ControlBox (Autodesk Fusion 360 design; units mm, degrees)
Autodesk Fusion 360 part; units mm, degrees
sketch "Sketch1" plane through (0, 0, 0) normal (0, 0, 1) x (1, 0, 0)
  line L0 (57.5, -137.5) -> (-57.5, -137.5)
  line L1 (-57.5, -137.5) -> (-57.5, 137.5)
  line L2 (-57.5, 137.5) -> (57.5, 137.5)
  line L3 (57.5, 137.5) -> (57.5, -137.5)
  line L4 (57.5, -137.5) -> (-57.5, 137.5) construction
  line L5 (-57.5, -137.5) -> (57.5, 137.5) construction
  line L6 (60, -140) -> (-60, -140)
  line L7 (-60, -140) -> (-60, 140)
  line L8 (-60, 140) -> (60, 140)
  line L9 (60, 140) -> (60, -140)
  line L10 (60, -140) -> (-60, 140) construction
  line L11 (-60, -140) -> (60, 140) construction
  dimension "d1" = 115
  dimension "d2" = 275
  dimension "d3" = 280
  dimension "d4" = 120
  constraint perpendicular L0 L1
  constraint parallel L0 L2
  constraint parallel L1 L3
  constraint horizontal L0
  constraint coincident L4 origin
  constraint coincident L5 origin
  constraint perpendicular L6 L7
  constraint parallel L6 L8
  constraint parallel L7 L9
  constraint horizontal L6
  constraint coincident L10 origin
  constraint coincident L11 origin
  measures "d1" distance of L1.end L2.end
  measures "d2" distance of L0.end L1.end
  measures "d3" distance of L6.end L7.end
  measures "d4" distance of L7.end L8.end
extrude "Extrude1" add sketch "Sketch1" along normal blind 2.5 contours L0 L1 L2 L3 | L6 L7 L8 L9
sketch "Sketch2" plane through (0, 0, 2.5) normal (0, 0, 1) x (1, 0, 0)
  line L0 (60, 140) -> (-60, 140)
  line L1 (-60, 140) -> (-60, -140)
  line L2 (-60, -140) -> (60, -140)
  line L3 (60, -140) -> (60, 140)
  line L4 (57.5, -137.5) -> (-57.5, -137.5)
  line L5 (-57.5, -137.5) -> (-57.5, 137.5)
  line L6 (-57.5, 137.5) -> (57.5, 137.5)
  line L7 (57.5, 137.5) -> (57.5, -137.5)
  line L8 (57.5, -137.5) -> (-57.5, 137.5) construction
  line L9 (-57.5, -137.5) -> (57.5, 137.5) construction
  dimension "d7" = 115
  dimension "d8" = 275
  constraint perpendicular L4 L5
  constraint parallel L4 L6
  constraint parallel L5 L7
  constraint horizontal L4
  constraint coincident L8 origin
  constraint coincident L9 origin
  measures "d7" distance of L5.end L6.end
  measures "d8" distance of L4.end L5.end
extrude "Extrude2" add sketch "Sketch2" along normal blind 50
sketch "Sketch3" plane through (0, -140, 0) normal (0, -1, 0) x (1, 0, 0)
  line L0 (-60, 0) -> (60, 0)
  line L1 (60, 0) -> (60, 52.5)
  line L2 (60, 52.5) -> (-60, 52.5)
  line L3 (-60, 52.5) -> (-60, 0)
extrude "Extrude3" add sketch "Sketch3" along normal blind 4
sketch "Sketch4" plane through (0, -144, 0) normal (0, -1, 0) x (1, 0, 0)
  line L0 (-60, 52.5) -> (-60, 0)
  line L1 (-60, 0) -> (60, 0)
  line L2 (60, 0) -> (60, 52.5)
  line L3 (60, 52.5) -> (-60, 52.5)
  line L4 (40.0928, 9.9) -> (13.3428, 9.9)
  line L5 (13.3428, 9.9) -> (13.3428, 28.5)
  line L6 (13.3428, 28.5) -> (40.0928, 28.5)
  line L7 (40.0928, 28.5) -> (40.0928, 9.9)
  line L8 (51.7178, 8.325) -> (1.7178, 8.325)
  line L9 (1.7178, 30.175) -> (51.7178, 30.175)
  line L10 (51.7178, 30.175) -> (51.7178, 8.325)
  line L11 (40.0928, 30.175) -> (42.8928, 30.175)
  line L12 (40.0928, 19.2) -> (46.5928, 19.2)
  line L13 (13.3428, 19.2) -> (6.8428, 19.2)
  circle A0 centre (6.8428, 19.2) radius 2
  circle A1 centre (46.5928, 19.2) radius 2
  line L14 (46.5928, 19.2) -> (51.7178, 19.25)
  line L15 (1.7178, 30.175) -> (1.7178, 8.325)
  line L16 (13.3428, 8.325) -> (1.7178, 19.25)
  line L17 (1.7178, 19.25) -> (13.3428, 30.175)
  line L18 (51.7178, 19.25) -> (40.0928, 8.325)
  line L19 (51.7178, 19.25) -> (40.0928, 30.175)
  point P0 (36.7178, 19.25)
  dimension "d42" = 50
  dimension "d43" = 21.85
  dimension "d44" = 26.75
  dimension "d45" = 18.6
  dimension "d46" = 6.5
  dimension "d47" = 6.5
  dimension "d48" = 4
  dimension "d49" = 4
  constraint horizontal L4
  constraint vertical L5
  constraint horizontal L6
  constraint vertical L7
  constraint parallel L8 L9
  constraint horizontal L8
  constraint midpoint L10 L14.end
  constraint coincident L9 L11.start
  constraint midpoint L7 L12.start
  constraint midpoint L5 L13.start
  constraint coincident L13.end A0.centre
  constraint coincident L12.end A1.centre
  constraint perpendicular L8 L15
  constraint coincident L8 L16.start
  constraint midpoint L15 L16.end
  constraint coincident L9 L17.end
  constraint coincident L8 L18.end
  constraint parallel L17 L18
  constraint parallel L16 L19
  measures "d42" horizontal distance of L9.start L9.end
  measures "d43" vertical distance of L8.end L9.start
  measures "d44" horizontal distance of L4.start L4.end
  measures "d45" vertical distance of L4.start L6.end
  measures "d46" distance of L12.start L12.end
  measures "d47" distance of L13.start L13.end
  measures "d48" diameter of A0
  measures "d49" diameter of A1
extrude "Extrude9" cut sketch "Sketch4" against normal blind 3.3 contours L8 L9 L16 L17 L18 L19
extrude "Extrude10" cut sketch "Sketch4" against normal up to surface (6.5 mm away) contours L4 L5 L6 L7 | L12 A1 L14 | L12 A1 L14 | A0
fillet "Fillet3" radius 2.5 2 edges at (51.7178, -142.35, 19.25) (1.7178, -142.35, 19.25)
fillet "Fillet4" radius 4 4 edges at (40.0928, -142.35, 8.325) (13.3428, -142.35, 8.325) (13.3428, -142.35, 30.175) (40.0928, -142.35, 30.175)
fillet "Fillet5" radius 3 4 edges at (13.3428, -139.1, 28.5) (40.0928, -139.1, 28.5) (13.3428, -139.1, 9.9) (40.0928, -139.1, 9.9)
sketch "Sketch6" plane through (0, 140, 0) normal (0, 1, 0) x (-1, 0, 0)
  line L0 (-60, 0) -> (60, 0)
  line L1 (60, 0) -> (60, 52.5)
  line L2 (60, 52.5) -> (-60, 52.5)
  line L3 (-60, 52.5) -> (-60, 0)
sketch "Sketch7" plane through (-60, 0, 0) normal (-1, 0, 0) x (0, 0, 1)
  line L0 (0, 140) -> (0, -144)
  line L1 (0, -144) -> (52.5, -144)
  line L2 (52.5, -144) -> (52.5, 140)
  line L3 (52.5, 140) -> (0, 140)
  line L4 (52.5, 140) -> (123.2107, 69.2893)
  line L5 (52.5, 140) -> (52.5, 135.8)
  line L6 (52.5, 135.8) -> (123.2107, 65.0893)
  line L7 (123.2107, 69.2893) -> (123.2107, 65.0893)
  constraint coincident L2.end L3.start
  constraint vertical L7
extrude "Extrude11" add sketch "Sketch7" against normal blind 120 contours L2 L4 L5 L6 L7
sketch "Sketch8" plane through (0, 96.25, 96.25) normal (0, 0.707107, 0.707107) x (1, 0, 0)
  line L0 (-60, 61.8718) -> (-60, -38.1282)
  line L1 (-60, -38.1282) -> (60, -38.1282)
  line L2 (60, -38.1282) -> (60, 61.8718)
  line L3 (60, 61.8718) -> (-60, 61.8718)
  line L4 (-36.55, 55.6) -> (56.55, 55.6)
  line L5 (56.55, 55.6) -> (56.55, -31.6)
  line L6 (56.55, -31.6) -> (-36.55, -31.6)
  line L7 (-36.55, -31.6) -> (-36.55, 55.6)
  circle A0 centre (54.05, -29.1) radius 1.5
  circle A1 centre (-33.95, -29.1) radius 1.5
  circle A2 centre (54.05, 35.9) radius 1.5
  circle A3 centre (-33.95, 35.9) radius 1.5
  circle A4 centre (-26.45, 45.9) radius 3.5
  line L8 (47.95, -22.1) -> (-23.55, -22.1)
  line L9 (-23.55, -22.1) -> (-23.55, 29.1)
  line L10 (-23.55, 29.1) -> (47.95, 29.1)
  line L11 (47.95, 29.1) -> (47.95, -22.1)
  point P0 (10, 12)
  dimension "d89" = 3
  dimension "d91" = 3
  dimension "d94" = 7
  constraint perpendicular L4 L5
  constraint parallel L4 L6
  constraint parallel L5 L7
  constraint horizontal L4
  constraint horizontal L8
  constraint vertical L9
  constraint horizontal L10
  constraint vertical L11
  measures "d89" diameter of A2
  measures "d91" diameter of A3
  measures "d94" diameter of A4
extrude "Extrude12" cut sketch "Sketch8" against normal up to surface (2.9698 mm away) contours A0 | A1 | A2 | A3 | A4 | L8 L9 L10 L11
sketch "Sketch9" plane through (-60, 0, 0) normal (-1, 0, 0) x (0, 0, 1)
  line L0 (0, 140) -> (0, -144)
  line L1 (0, -144) -> (52.5, -144)
  line L2 (52.5, -144) -> (52.5, 135.8)
  line L3 (52.5, 135.8) -> (123.2107, 65.0893)
  line L4 (123.2107, 65.0893) -> (123.2107, 69.2893)
  line L5 (123.2107, 69.2893) -> (52.5, 140)
  line L6 (52.5, 140) -> (0, 140)
  line L7 (52.5, -144) -> (138, -144)
  line L8 (123.2107, 65.0893) -> (123.2107, -170)
  line L9 (123.2107, -144) -> (125.7107, -144)
  line L10 (125.7107, -144) -> (125.7107, 78)
  line L11 (123.2107, 69.2893) -> (125.7107, 66.7893)
  line L12 (52.5, -144) -> (52.5, -141.5)
  line L13 (52.5, -141.5) -> (123.2107, -141.5)
  dimension "d101" = 2.5
  dimension "d102" = 2.5
  constraint coincident L1.end L2.start
  constraint perpendicular L2 L7
  constraint coincident L3.end L4.start
  constraint perpendicular L7 L8
  constraint coincident L8 L9.start
  constraint coincident L7 L9.start
  constraint perpendicular L9 L10
  constraint coincident L4.end L5.start
  constraint coincident L10 L11.end
  constraint parallel L5 L11
  constraint coincident L8 L13.end
  constraint perpendicular L8 L13
  measures "d101" distance of L9.start L9.end
  measures "d102" distance of L1.end L12.end
extrude "Extrude13" add sketch "Sketch9" against normal blind 120 contours L2 L7 L8 L12 L13 | L4 L7 L8 L9 L10 L11
sketch "Sketch10" plane through (-60, 0, 0) normal (-1, 0, 0) x (0, 0, 1)
  line L0 (125.7107, 66.7893) -> (52.5, 140)
  line L1 (52.5, 140) -> (0, 140)
  line L2 (0, 140) -> (0, -144)
  line L3 (0, -144) -> (125.7107, -144)
  line L4 (125.7107, -144) -> (125.7107, 66.7893)
  line L5 (123.2107, 65.0893) -> (123.2107, -141.5)
  line L6 (123.2107, -141.5) -> (52.5, -141.5)
  line L7 (52.5, -141.5) -> (52.5, 135.8)
  line L8 (52.5, 135.8) -> (123.2107, 65.0893)
extrude "Extrude14" add sketch "Sketch10" against normal blind 3.5 contours L5 L6 L7 L8
sketch "Sketch11" plane through (60, 0, 0) normal (1, 0, 0) x (0, 0, -1)
  line L0 (-123.2107, 65.0893) -> (-52.5, 135.8)
  line L1 (-52.5, 135.8) -> (-52.5, -141.5)
  line L2 (-52.5, -141.5) -> (-123.2107, -141.5)
  line L3 (-123.2107, -141.5) -> (-123.2107, 65.0893)
  line L4 (-52.5, 140) -> (-125.7107, 66.7893)
  line L5 (-125.7107, 66.7893) -> (-125.7107, -144)
  line L6 (-125.7107, -144) -> (0, -144)
  line L7 (0, -144) -> (0, 140)
  line L8 (0, 140) -> (-52.5, 140)
extrude "Extrude15" add sketch "Sketch11" against normal blind 2.5 contours L0 L1 L2 L3
sketch "Sketch12" plane through (0, -144, 0) normal (0, -1, 0) x (1, 0, 0)
  line L0 (-60, 125.7107) -> (-60, 0)
  line L1 (-60, 0) -> (60, 0)
  line L2 (60, 0) -> (60, 125.7107)
  line L3 (60, 125.7107) -> (-60, 125.7107)
  line L4 (41.2475, 29.0898) -> (49.7793, 21.0718)
  arc A0 (49.7793, 17.4282) -> (49.7793, 21.0718) centre (48.0672, 19.25) ccw
  line L5 (49.7793, 17.4282) -> (41.2475, 9.4102)
  arc A1 (38.5082, 8.325) -> (41.2475, 9.4102) centre (38.5082, 12.325) ccw
  line L6 (38.5082, 8.325) -> (14.9274, 8.325)
  arc A2 (12.188, 9.4102) -> (14.9274, 8.325) centre (14.9274, 12.325) ccw
  line L7 (12.188, 9.4102) -> (3.6562, 17.4282)
  arc A3 (3.6562, 21.0718) -> (3.6562, 17.4282) centre (5.3683, 19.25) ccw
  line L8 (3.6562, 21.0718) -> (12.188, 29.0898)
  arc A4 (14.9274, 30.175) -> (12.188, 29.0898) centre (14.9274, 26.175) ccw
  line L9 (14.9274, 30.175) -> (38.5082, 30.175)
  arc A5 (41.2475, 29.0898) -> (38.5082, 30.175) centre (38.5082, 26.175) ccw
  circle A6 centre (-42.9289, 108.6396) radius 10
extrude "Extrude16" cut sketch "Sketch12" against normal blind 2.5 contours A6
